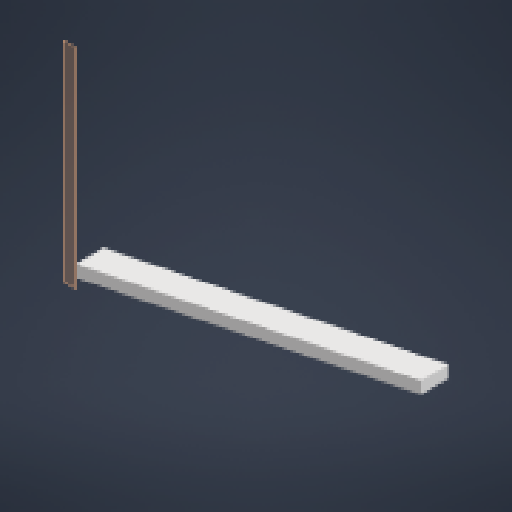
# Autodesk Inventor part: Upper Ear Diagonals
Saved by Autodesk Inventor 2027 (Build 310192000, 192)
## iProperties
Created: 2026-10-18
Part Number: Upper Ear Diagonals
Material: Generic
Document SubType Name: Modeling
Designer: lucas
Density: 1 g/cm^3
Appearance: Default
Author: lucas
Autodesk Inventor part; units mm, degrees
ref_plane "YZ Plane" through (0, 0, 0) normal (1, 0, 0) x (0, 1, 0)
ref_plane "XZ Plane" through (0, 0, 0) normal (0, 1, 0) x (-1, 0, 0)
ref_plane "XY Plane" through (0, 0, 0) normal (0, 0, 1) x (1, 0, 0)
ref_plane "Work Plane1" through (0, 0, 0) normal (0, 0, 1) x (1, 0, 0)
sketch "Sketch1" plane through (0, 0, 0) normal (0, 0, 1) x (1, 0, 0)
  line L0 (38.1, -609.6) -> (1143, -381)
  line L1 (747.043, -424.0152) -> (223.3826, -532.3588)
  line L2 (223.3826, -532.3588) -> (38.1, -570.6931)
  line L3 (38.1, -570.6931) -> (38.1, -609.6)
  line L4 (747.043, -424.0152) -> (1143, -342.0931)
  line L5 (1143, -342.0931) -> (1143, -381)
  point P0 (0, 0)
  dimension "d0" = 38.1
  constraints: 12 end point, 3 parallel, 2 vertical, 2 other
  measures "d0" distance between parallel lines of L0 L1
extrude "Extrusion1" add sketch "Sketch1" against normal blind 88.9
body "Solid1"
